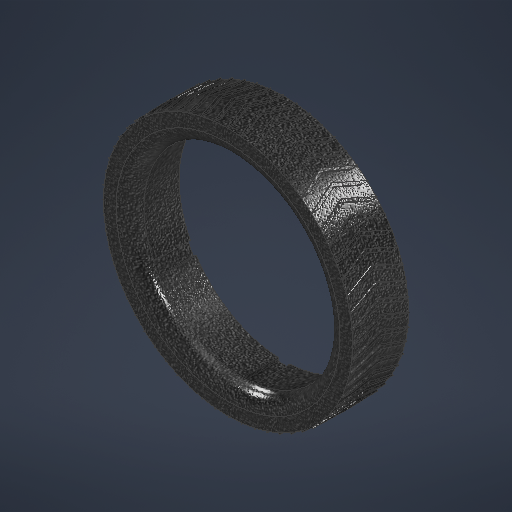
# Autodesk Inventor part: roues_3d_moteur_tpu
Saved by Autodesk Inventor 2026 (Build 300175000, 175)
## iProperties
Created: 2025-05-23
Part Number: roues_3d_moteur_tpu
Material: Generisch
Document SubType Name: Modeling
Designer: karle
Density: 1 g/cm^3
Appearance: Vorgabe
Author: karle
Autodesk Inventor part; units mm, degrees
ref_plane "YZ Plane" through (0, 0, 0) normal (1, 0, 0) x (0, 1, 0)
sketch "Skizze1" plane through (0, 0, 0) normal (0, 0, 1) x (1, 0, 0)
  circle A0 centre (0, 0) radius 37.5
  circle A1 centre (0, 0) radius 44.5
  dimension "d0" = 89
  dimension "d1" = 75
  constraints: 2 centre point, 2 coincident
  measures "d0" diameter of A1
  measures "d1" diameter of A0
extrude "Extrusion1" add sketch "Skizze1" along normal mid plane 15
sketch "Skizze2" plane through (0, 0, 7.5) normal (0, 0, 1) x (1, 0, 0)
  circle A0 centre (0, 0) radius 35
  circle A1 centre (0, 0) radius 44.5
  dimension "d4" = 70
  dimension "d7" = 89
  constraints: 2 centre point, 2 coincident
  measures "d4" diameter of A0
  measures "d7" diameter of A1
extrude "Extrusion2" add sketch "Skizze2" along normal blind 5
ref_plane "Arbeitsebene1" through (0, 44.5, 0) normal (0, 1, 0) x (-1, 0, 0)
sketch "Skizze7" plane through (0, 44.5, 0) normal (0, 1, 0) x (-1, 0, 0)
  line L0 (44.5, 12.5) -> (-44.5, 12.5) projected
  line L1 (0, 12.5) -> (4.08, 2.5)
  line L2 (4.08, 2.5) -> (0, -7.5)
  line L3 (37.5, -7.5) -> (-37.5, -7.5) projected
  line L4 (0, -4.8529) -> (3, 2.5)
  line L5 (3, 2.5) -> (0, 9.8529)
  line L6 (0, 9.8529) -> (0, 12.5)
  line L7 (0, -4.8529) -> (0, -7.5)
  point P0 (0, 0)
  point P1 (2.04, 7.5)
  point P2 (1.5, -1.1764)
  dimension "d21" = 10
  dimension "d22" = 1
  dimension "d23" = 1
  dimension "d24" = 3
  dimension "d30" = 10
  constraints: 12 end point, 4 midpoint, 2 parallel, 1 collinear, 1 perpendicular, 1 point on line
  measures "d21" distance from line of L3 L1.end
  measures "d22" distance from line of point (2.04, 7.5) L5
  measures "d23" distance from line of L2 point (1.5, -1.176)
  measures "d24" horizontal distance of point (0, 0) L4.end
  measures "d30" distance from line of L0 L1.end
extrude "Extrusion3" add sketch "Skizze7" along normal mid plane 1
pattern_circular "Runde Anordnung1" count 60 over 360 about axis through (0, 0, -10) along (0, 0, 1) of "Extrusion3"
fillet "Rundung1" radius 5 1 edges at (-35, 0, 12.5)
ref_plane "Arbeitsebene2" through (0, 37.5, 0) normal (0, 1, 0) x (-1, 0, 0)
sketch "Skizze9" plane through (0, 37.5, 0) normal (0, 1, 0) x (-1, 0, 0)
  line L0 (40, 12.5) -> (-40, 12.5) projected
  line L1 (-2.1, 12.5) -> (2.1, 12.5)
  line L2 (37.5, -7.5) -> (-37.5, -7.5) projected
  line L3 (-37.5, 7.5) -> (37.5, 7.5) projected
  line L4 (2.1, -7.5) -> (-2.1, -7.5)
  line L5 (-2.1, -7.5) -> (-2.1, 7.5)
  line L6 (-2.1, 7.5) -> (2.1, 7.5)
  line L7 (2.1, 7.5) -> (2.1, -7.5)
  point P0 (0, 0)
  point P1 (0, 12.5)
  dimension "d37" = 4.2
  dimension "d38" = 2.1
  constraints: 10 end point, 3 point on line, 2 parallel, 1 horizontal, 1 midpoint, 1 perpendicular
  measures "d37" distance between parallel lines of L7 L5
  measures "d38" distance from line of point (0, 0) L7
extrude "Extrusion4" cut sketch "Skizze9" along normal mid plane 2.2
pattern_circular "Runde Anordnung2" count 6 over 360 about axis through (0, 0, -10) along (0, 0, 1) of "Extrusion4"
